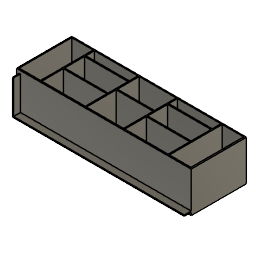
Front Counter - R1 (Autodesk Fusion 360 design; units mm, degrees)
Autodesk Fusion 360 part; units mm, degrees
sketch "Sketch1" plane through (0, 0, 0) normal (0, 1, 0) x (1, 0, 0)
  line L0 (0, 0) -> (240, 0)
  line L1 (240, 0) -> (240, -55.5)
  line L2 (240, -55.5) -> (0, -55.5)
  line L3 (0, -55.5) -> (0, 0)
  dimension "d1" = 240
  dimension "d2" = 55.5
  constraint horizontal L0
  constraint vertical L1
  constraint horizontal L2
  constraint vertical L3
  constraint coincident L0.start L3.end
  measures "d1" distance of L0.start L0.end
  measures "d2" distance of L0.start L2.end
extrude "Extrude1" add sketch "Sketch1" along normal blind 76
sketch "Sketch2" plane through (0, 0, 55.5) normal (0, 0, 1) x (-1, 0, 0)
  line L0 (0, 0) -> (-240, 0)
  line L1 (-240, 0) -> (-240, -76)
  line L2 (-240, -76) -> (0, -76)
  line L3 (0, -76) -> (0, 0)
  line L4 (0, -76) -> (-1.6, -76)
  line L5 (-1.6, -76) -> (-1.6, -74.4)
  line L6 (-1.6, -74.4) -> (-31.2, -74.4)
  line L7 (-31.2, -74.4) -> (-31.2, -1.9)
  line L8 (-1.6, -74.4) -> (-1.6, -1.9)
  line L9 (-1.6, -1.9) -> (-31.2, -1.9)
  dimension "d5" = 1.6
  dimension "d6" = 1.6
  dimension "d7" = 29.6
  dimension "d8" = 72.5
  dimension "d9" = 72.5
  constraint coincident L2.end L3.start
  constraint perpendicular L3 L4
  constraint vertical L5
  constraint perpendicular L5 L6
  constraint perpendicular L6 L7
  constraint perpendicular L6 L8
  measures "d5" distance of L2.end L4.end
  measures "d6" distance of L4.end L5.end
  measures "d7" distance of L5.end L6.end
  measures "d8" distance of L6.end L7.end
  measures "d9" distance of L5.end L8.end
extrude "Extrude2" cut sketch "Sketch2" against normal blind 54.5 contours L6 L7 L8 L9
sketch "Sketch3" plane through (0, 0, 55.5) normal (0, 0, 1) x (-1, 0, 0)
  line L0 (-31.2, -1.9) -> (-1.6, -1.9)
  line L1 (-1.6, -1.9) -> (-1.6, -74.4)
  line L2 (-1.6, -74.4) -> (-31.2, -74.4)
  line L3 (-31.2, -74.4) -> (-31.2, -1.9)
  line L4 (0, 0) -> (-240, 0)
  line L5 (-240, 0) -> (-240, -76)
  line L6 (-240, -76) -> (0, -76)
  line L7 (0, -76) -> (0, 0)
  line L8 (-31.2, -1.9) -> (-32.8, -1.9)
  line L9 (-32.8, -1.9) -> (-92.6, -1.9)
  line L10 (-32.8, -1.9) -> (-32.8, -74.4)
  line L11 (-92.6, -1.9) -> (-92.6, -74.4)
  line L12 (-32.8, -74.4) -> (-92.6, -74.4)
  dimension "d12" = 1.6
  dimension "d13" = 59.8
  dimension "d14" = 72.5
  dimension "d15" = 72.5
  constraint coincident L0.start L3.end
  constraint horizontal L8
  constraint perpendicular L3 L9
  constraint perpendicular L9 L10
  constraint perpendicular L9 L11
  measures "d12" distance of L0.start L8.end
  measures "d13" distance of L8.end L9.end
  measures "d14" distance of L8.end L10.end
  measures "d15" distance of L9.end L11.end
extrude "Extrude3" cut sketch "Sketch3" against normal blind 54.5 contours L9 L10 L11 L12
sketch "Sketch4" plane through (0, 0, 55.5) normal (0, 0, 1) x (-1, 0, 0)
  line L0 (-92.6, -74.4) -> (-92.6, -1.9)
  line L1 (-92.6, -1.9) -> (-32.8, -1.9)
  line L2 (-32.8, -1.9) -> (-32.8, -74.4)
  line L3 (-32.8, -74.4) -> (-92.6, -74.4)
  line L4 (-31.2, -1.9) -> (-1.6, -1.9)
  line L5 (-1.6, -1.9) -> (-1.6, -74.4)
  line L6 (-1.6, -74.4) -> (-31.2, -74.4)
  line L7 (-31.2, -74.4) -> (-31.2, -1.9)
  line L8 (0, 0) -> (-240, 0)
  line L9 (-240, 0) -> (-240, -76)
  line L10 (-240, -76) -> (0, -76)
  line L11 (0, -76) -> (0, 0)
  line L12 (-92.6, -74.4) -> (-94.2, -74.4)
  line L13 (-94.2, -74.4) -> (-145.2, -74.4)
  line L14 (-145.2, -74.4) -> (-145.2, -1.9)
  line L15 (-145.2, -1.9) -> (-94.2, -1.9)
  line L16 (-94.2, -1.9) -> (-94.2, -74.4)
  line L17 (-145.2, -74.4) -> (-146.8, -74.4)
  line L18 (-146.8, -74.4) -> (-206.6, -74.4)
  line L19 (-206.6, -74.4) -> (-206.6, -1.9)
  line L20 (-206.6, -1.9) -> (-146.8, -1.9)
  line L21 (-146.8, -1.9) -> (-146.8, -74.4)
  line L22 (-206.6, -74.4) -> (-208.2, -74.4)
  line L23 (-208.2, -74.4) -> (-237.8, -74.4)
  line L24 (-237.8, -74.4) -> (-237.8, -1.9)
  line L25 (-237.8, -1.9) -> (-208.2, -1.9)
  line L26 (-208.2, -1.9) -> (-208.2, -74.4)
  dimension "d18" = 1.6
  dimension "d19" = 51
  dimension "d20" = 72.5
  dimension "d21" = 1.6
  dimension "d22" = 59.8
  dimension "d23" = 72.5
  dimension "d24" = 1.6
  dimension "d25" = 29.6
  dimension "d26" = 72.5
  constraint coincident L0.start L3.end
  constraint horizontal L12
  constraint horizontal L13
  constraint vertical L14
  constraint horizontal L15
  constraint vertical L16
  constraint horizontal L17
  constraint horizontal L18
  constraint vertical L19
  constraint horizontal L20
  constraint vertical L21
  constraint horizontal L22
  constraint horizontal L23
  constraint vertical L24
  constraint horizontal L25
  constraint vertical L26
  measures "d18" distance of L0.start L12.end
  measures "d19" distance of L12.end L13.end
  measures "d20" distance of L12.end L15.end
  measures "d21" distance of L13.end L17.end
  measures "d22" distance of L17.end L18.end
  measures "d23" distance of L17.end L20.end
  measures "d24" distance of L18.end L22.end
  measures "d25" distance of L22.end L23.end
  measures "d26" distance of L22.end L25.end
extrude "Extrude4" cut sketch "Sketch4" against normal blind 54.5 contours L13 L14 L15 L16 | L18 L19 L20 L21 | L23 L24 L25 L26
sketch "Sketch5" plane through (0, 0, 55.5) normal (0, 0, 1) x (-1, 0, 0)
  line L0 (-145.2, -74.4) -> (-145.2, -1.9)
  line L1 (-145.2, -1.9) -> (-94.2, -1.9)
  line L2 (-94.2, -1.9) -> (-94.2, -74.4)
  line L3 (-94.2, -74.4) -> (-145.2, -74.4)
  line L4 (-237.8, -74.4) -> (-237.8, -1.9)
  line L5 (-237.8, -1.9) -> (-208.2, -1.9)
  line L6 (-208.2, -1.9) -> (-208.2, -74.4)
  line L7 (-208.2, -74.4) -> (-237.8, -74.4)
  line L8 (-206.6, -74.4) -> (-206.6, -1.9)
  line L9 (-206.6, -1.9) -> (-146.8, -1.9)
  line L10 (-146.8, -1.9) -> (-146.8, -74.4)
  line L11 (-146.8, -74.4) -> (-206.6, -74.4)
  line L12 (-92.6, -74.4) -> (-92.6, -1.9)
  line L13 (-92.6, -1.9) -> (-32.8, -1.9)
  line L14 (-32.8, -1.9) -> (-32.8, -74.4)
  line L15 (-32.8, -74.4) -> (-92.6, -74.4)
  line L16 (-31.2, -1.9) -> (-1.6, -1.9)
  line L17 (-1.6, -1.9) -> (-1.6, -74.4)
  line L18 (-1.6, -74.4) -> (-31.2, -74.4)
  line L19 (-31.2, -74.4) -> (-31.2, -1.9)
  line L20 (0, 0) -> (-240, 0)
  line L21 (-240, 0) -> (-240, -76)
  line L22 (-240, -76) -> (0, -76)
  line L23 (0, -76) -> (0, 0)
  line L24 (-94.2, -74.4) -> (-94.2, -44.4)
  line L25 (-94.2, -44.4) -> (-145.2, -44.4)
  line L26 (-145.2, -44.4) -> (-145.2, -42.8)
  line L27 (-145.2, -42.8) -> (-94.2, -42.8)
  line L28 (-94.2, -42.8) -> (-94.2, -44.4)
  dimension "d29" = 30
  dimension "d30" = 51
  dimension "d31" = 1.6
  constraint coincident L2.end L3.start
  constraint perpendicular L3 L24
  constraint horizontal L25
  constraint vertical L26
  constraint horizontal L27
  constraint vertical L28
  measures "d29" distance of L2.end L24.end
  measures "d30" distance of L24.end L25.end
  measures "d31" distance of L24.end L27.end
extrude "Extrude5" add sketch "Sketch5" against normal blind 54.5 contours L0 L2 L25 L26 L27 L28
sketch "Sketch6" plane through (0, 0, 55.5) normal (0, 0, 1) x (-1, 0, 0)
  line L0 (-145.2, -42.8) -> (-145.2, -1.9)
  line L1 (-145.2, -1.9) -> (-94.2, -1.9)
  line L2 (-94.2, -1.9) -> (-94.2, -42.8)
  line L3 (-94.2, -42.8) -> (-145.2, -42.8)
  line L4 (-145.2, -44.4) -> (-94.2, -44.4)
  line L5 (-94.2, -44.4) -> (-94.2, -74.4)
  line L6 (-94.2, -74.4) -> (-145.2, -74.4)
  line L7 (-145.2, -74.4) -> (-145.2, -44.4)
  line L8 (-237.8, -74.4) -> (-237.8, -1.9)
  line L9 (-237.8, -1.9) -> (-208.2, -1.9)
  line L10 (-208.2, -1.9) -> (-208.2, -74.4)
  line L11 (-208.2, -74.4) -> (-237.8, -74.4)
  line L12 (-206.6, -74.4) -> (-206.6, -1.9)
  line L13 (-206.6, -1.9) -> (-146.8, -1.9)
  line L14 (-146.8, -1.9) -> (-146.8, -74.4)
  line L15 (-146.8, -74.4) -> (-206.6, -74.4)
  line L16 (-92.6, -74.4) -> (-92.6, -1.9)
  line L17 (-92.6, -1.9) -> (-32.8, -1.9)
  line L18 (-32.8, -1.9) -> (-32.8, -74.4)
  line L19 (-32.8, -74.4) -> (-92.6, -74.4)
  line L20 (-31.2, -1.9) -> (-1.6, -1.9)
  line L21 (-1.6, -1.9) -> (-1.6, -74.4)
  line L22 (-1.6, -74.4) -> (-31.2, -74.4)
  line L23 (-31.2, -74.4) -> (-31.2, -1.9)
  line L24 (0, 0) -> (-240, 0)
  line L25 (-240, 0) -> (-240, -76)
  line L26 (-240, -76) -> (0, -76)
  line L27 (0, -76) -> (0, 0)
  line L28 (-32.8, -74.4) -> (-32.8, -62.4)
  line L29 (-32.8, -62.4) -> (-92.6, -62.4)
  line L30 (-92.6, -62.4) -> (-92.6, -60.8)
  line L31 (-92.6, -60.8) -> (-32.8, -60.8)
  line L32 (-32.8, -60.8) -> (-32.8, -62.4)
  line L33 (-32.8, -60.8) -> (-32.8, -33.3)
  line L34 (-32.8, -33.3) -> (-92.6, -33.3)
  line L35 (-92.6, -33.3) -> (-92.6, -31.7)
  line L36 (-92.6, -31.7) -> (-32.8, -31.7)
  line L37 (-32.8, -31.7) -> (-32.8, -33.3)
  dimension "d34" = 12
  dimension "d35" = 1.6
  dimension "d36" = 27.5
  dimension "d37" = 1.6
  constraint coincident L18.end L19.start
  constraint perpendicular L19 L28
  constraint horizontal L29
  constraint vertical L30
  constraint horizontal L31
  constraint vertical L32
  constraint perpendicular L31 L33
  constraint horizontal L34
  constraint vertical L35
  constraint horizontal L36
  constraint vertical L37
  measures "d34" distance of L18.end L28.end
  measures "d35" distance of L28.end L31.end
  measures "d36" distance of L31.end L33.end
  measures "d37" distance of L33.end L36.end
extrude "Extrude6" add sketch "Sketch6" against normal blind 54.5 contours L16 L18 L29 L30 L31 L32 | L16 L18 L34 L35 L36 L37
sketch "Sketch7" plane through (0, 0, 55.5) normal (0, 0, 1) x (-1, 0, 0)
  line L0 (-32.8, -33.3) -> (-32.8, -60.8)
  line L1 (-32.8, -60.8) -> (-92.6, -60.8)
  line L2 (-92.6, -60.8) -> (-92.6, -33.3)
  line L3 (-92.6, -33.3) -> (-32.8, -33.3)
  line L4 (-32.8, -31.7) -> (-92.6, -31.7)
  line L5 (-92.6, -31.7) -> (-92.6, -1.9)
  line L6 (-92.6, -1.9) -> (-32.8, -1.9)
  line L7 (-32.8, -1.9) -> (-32.8, -31.7)
  line L8 (-145.2, -42.8) -> (-145.2, -1.9)
  line L9 (-145.2, -1.9) -> (-94.2, -1.9)
  line L10 (-94.2, -1.9) -> (-94.2, -42.8)
  line L11 (-94.2, -42.8) -> (-145.2, -42.8)
  line L12 (-145.2, -44.4) -> (-94.2, -44.4)
  line L13 (-94.2, -44.4) -> (-94.2, -74.4)
  line L14 (-94.2, -74.4) -> (-145.2, -74.4)
  line L15 (-145.2, -74.4) -> (-145.2, -44.4)
  line L16 (-237.8, -74.4) -> (-237.8, -1.9)
  line L17 (-237.8, -1.9) -> (-208.2, -1.9)
  line L18 (-208.2, -1.9) -> (-208.2, -74.4)
  line L19 (-208.2, -74.4) -> (-237.8, -74.4)
  line L20 (-206.6, -74.4) -> (-206.6, -1.9)
  line L21 (-206.6, -1.9) -> (-146.8, -1.9)
  line L22 (-146.8, -1.9) -> (-146.8, -74.4)
  line L23 (-146.8, -74.4) -> (-206.6, -74.4)
  line L24 (-92.6, -62.4) -> (-32.8, -62.4)
  line L25 (-32.8, -62.4) -> (-32.8, -74.4)
  line L26 (-32.8, -74.4) -> (-92.6, -74.4)
  line L27 (-92.6, -74.4) -> (-92.6, -62.4)
  line L28 (-31.2, -1.9) -> (-1.6, -1.9)
  line L29 (-1.6, -1.9) -> (-1.6, -74.4)
  line L30 (-1.6, -74.4) -> (-31.2, -74.4)
  line L31 (-31.2, -74.4) -> (-31.2, -1.9)
  line L32 (0, 0) -> (-240, 0)
  line L33 (-240, 0) -> (-240, -76)
  line L34 (-240, -76) -> (0, -76)
  line L35 (0, -76) -> (0, 0)
  line L36 (-146.8, -74.4) -> (-146.8, -62.4)
  line L37 (-146.8, -62.4) -> (-206.6, -62.4)
  line L38 (-206.6, -62.4) -> (-206.6, -60.8)
  line L39 (-206.6, -60.8) -> (-146.8, -60.8)
  line L40 (-146.8, -60.8) -> (-146.8, -62.4)
  line L41 (-146.8, -60.8) -> (-146.8, -33.3)
  line L42 (-146.8, -33.3) -> (-206.6, -33.3)
  line L43 (-206.6, -33.3) -> (-206.6, -31.7)
  line L44 (-206.6, -31.7) -> (-146.8, -31.7)
  line L45 (-146.8, -31.7) -> (-146.8, -33.3)
  dimension "d40" = 12
  dimension "d41" = 1.6
  dimension "d42" = 27.5
  dimension "d43" = 1.6
  constraint coincident L22.end L23.start
  constraint perpendicular L12 L36
  constraint horizontal L37
  constraint vertical L38
  constraint horizontal L39
  constraint vertical L40
  constraint perpendicular L39 L41
  constraint horizontal L42
  constraint vertical L43
  constraint horizontal L44
  constraint vertical L45
  measures "d40" distance of L22.end L36.end
  measures "d41" distance of L36.end L39.end
  measures "d42" distance of L39.end L41.end
  measures "d43" distance of L41.end L44.end
extrude "Extrude7" add sketch "Sketch7" against normal blind 54.5 contours L20 L22 L37 L38 L39 L40 | L20 L22 L42 L43 L44 L45
sketch "Sketch8" plane through (0, 0, 0) normal (0, -1, 0) x (1, 0, 0)
  line L0 (240, 55.5) -> (0, 55.5)
  line L1 (0, 55.5) -> (0, 0)
  line L2 (0, 0) -> (240, 0)
  line L3 (240, 0) -> (240, 55.5)
  line L4 (240, 0) -> (240, 4)
  line L5 (240, 4) -> (236, 4)
  line L6 (236, 4) -> (4, 4)
  line L7 (4, 4) -> (4, 5.6)
  line L8 (4, 5.6) -> (236, 5.6)
  line L9 (236, 5.6) -> (236, 4)
  dimension "d46" = 4
  dimension "d47" = 4
  dimension "d48" = 232
  dimension "d49" = 1.6
  constraint coincident L2.end L3.start
  constraint vertical L4
  constraint perpendicular L4 L5
  constraint horizontal L6
  constraint vertical L7
  constraint horizontal L8
  constraint vertical L9
  measures "d46" distance of L2.end L4.end
  measures "d47" distance of L4.end L5.end
  measures "d48" distance of L5.end L6.end
  measures "d49" distance of L5.end L8.end
extrude "Extrude8" add sketch "Sketch8" along normal blind 9.5 contours L6 L7 L8 L9
sketch "Sketch9" plane through (0, 0, 0) normal (0, -1, 0) x (1, 0, 0)
  line L0 (236, 5.6) -> (236, 4)
  line L1 (236, 4) -> (4, 4)
  line L2 (4, 4) -> (4, 5.6)
  line L3 (4, 5.6) -> (236, 5.6)
  line L4 (240, 55.5) -> (0, 55.5)
  line L5 (0, 55.5) -> (0, 0)
  line L6 (0, 0) -> (240, 0)
  line L7 (240, 0) -> (240, 55.5)
  line L8 (4, 4) -> (5.6, 4)
  line L9 (5.6, 4) -> (5.6, 51.5)
  line L10 (5.6, 51.5) -> (4, 51.5)
  line L11 (4, 51.5) -> (4, 4)
  dimension "d52" = 1.6
  dimension "d53" = 47.5
  constraint horizontal L8
  constraint vertical L9
  constraint horizontal L10
  constraint vertical L11
  constraint coincident L1.end L2.start
  measures "d52" distance of L1.end L8.end
  measures "d53" distance of L1.end L10.end
extrude "Extrude9" add sketch "Sketch9" along normal blind 9.5 contours L3 L9 L10 L11
sketch "Sketch10" plane through (0, -9.5, 0) normal (0, -1, 0) x (1, 0, 0)
  line L0 (236, 5.6) -> (5.6, 5.6)
  line L1 (5.6, 5.6) -> (5.6, 51.5)
  line L2 (5.6, 51.5) -> (4, 51.5)
  line L3 (4, 51.5) -> (4, 4)
  line L4 (4, 4) -> (236, 4)
  line L5 (236, 4) -> (236, 5.6)
  line L6 (236, 5.6) -> (240, 5.6)
  line L7 (240, 5.6) -> (240, 4)
  line L8 (240, 4) -> (236, 4)
  line L9 (236, 4) -> (236, 5.6)
  constraint horizontal L6
  constraint vertical L7
  constraint horizontal L8
  constraint vertical L9
  constraint coincident L0.start L5.end
extrude "Extrude10" add sketch "Sketch10" against normal blind 9.5 contours L5 L6 L7 L8 L9
